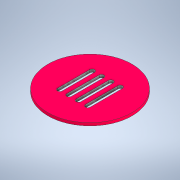
# Autodesk Inventor part: CAPAC_FELINAR_NR_4
Saved by Autodesk Inventor 2022.6 (Build 266554000, 554)
## iProperties
Created: 2025-06-10
Part Number: CAPAC_FELINAR_NR_4
Material: Generic
Document SubType Name: Modeling
Designer: Dragos Macovei
Density: 1 g/cm^3
Appearance: Default
Author: Dragos Macovei
Autodesk Inventor part; units mm, degrees
ref_plane "YZ Plane" through (0, 0, 0) normal (1, 0, 0) x (0, 1, 0)
ref_plane "XZ Plane" through (0, 0, 0) normal (0, 1, 0) x (-1, 0, 0)
ref_plane "XY Plane" through (0, 0, 0) normal (0, 0, 1) x (1, 0, 0)
sketch "Sketch1" plane through (0, 0, 0) normal (0, 1, 0) x (-1, 0, 0)
  circle A0 centre (0, 0) radius 90
  dimension "d0" = 180
  constraints: 1 centre point, 1 coincident
  measures "d0" diameter of A0
extrude "Extrusion1" add sketch "Sketch1" along normal blind 6
sketch "Sketch7" plane through (0, 6, 0) normal (0, 1, 0) x (1, 0, 0)
  circle A0 centre (0, 0) radius 60 construction
  circle A1 centre (30, 34.7214) radius 5
  circle A2 centre (30, -34.7214) radius 5
  line L0 (35, -34.7214) -> (35, 34.7214)
  line L1 (25, 34.7214) -> (25, -34.7214)
  line L2 (-40, 44.7214) -> (40, 44.7214)
  line L3 (40, 44.7214) -> (40, -44.7214)
  line L4 (40, -44.7214) -> (-40, -44.7214)
  line L5 (-40, -44.7214) -> (-40, 44.7214)
  circle A3 centre (-30, 34.7214) radius 5
  circle A4 centre (-30, -34.7214) radius 5
  line L6 (-25, -34.7214) -> (-25, 34.7214)
  line L7 (-35, 34.7214) -> (-35, -34.7214)
  circle A5 centre (-10, 34.7214) radius 5
  circle A6 centre (-10, -34.7214) radius 5
  line L8 (-5, -34.7214) -> (-5, 34.7214)
  line L9 (-15, 34.7214) -> (-15, -34.7214)
  circle A7 centre (10, -34.7214) radius 5
  line L10 (15, -34.7214) -> (15, 34.7214)
  line L11 (5, 34.7214) -> (5, -34.7214)
  circle A8 centre (10, 34.7214) radius 5
  dimension "d25" = 120
  dimension "d26" = 10
  dimension "d27" = 10
  dimension "d28" = 10
  dimension "d29" = 10
  dimension "d30" = 10
  dimension "d31" = 10
  dimension "d32" = 10
  dimension "d33" = 10
  dimension "d34" = 10
  dimension "d35" = 10
  dimension "d36" = 10
  dimension "d37" = 10
  dimension "d38" = 10
  dimension "d39" = 10
  dimension "d40" = 20
  dimension "d41" = 20
  dimension "d42" = 10
  dimension "d43" = 10
  dimension "d44" = 10
  dimension "d45" = 10
  dimension "d46" = 20
  dimension "d47" = 20
  dimension "d48" = 10
  dimension "d49" = 10
  dimension "d50" = 20
  constraints: 24 end point, 19 point on circle, 16 tangent, 9 centre point, 2 parallel, 1 coincident, 1 horizontal, 1 perpendicular
  measures "d25" diameter of A0
  measures "d26" diameter of A1
  measures "d27" diameter of A2
  measures "d28" distance from line of L3 A1.centre
  measures "d29" distance from line of A1.centre L2
  measures "d30" distance from line of L3 A2.centre
  measures "d31" distance from line of L4 A2.centre
  measures "d32" diameter of A3
  measures "d33" diameter of A4
  measures "d34" distance from line of L5 A3.centre
  measures "d35" distance from line of L5 A4.centre
  measures "d36" distance from line of L4 A4.centre
  measures "d37" distance from line of L2 A3.centre
  measures "d38" diameter of A5
  measures "d39" diameter of A6
  measures "d40" distance of A3.centre A5.centre
  measures "d41" distance of A4.centre A6.centre
  measures "d42" distance from line of A5.centre L2
  measures "d43" distance from line of A6.centre L4
  measures "d44" diameter of A8
  measures "d45" diameter of A7
  measures "d46" distance of A6.centre A7.centre
  measures "d47" distance of A5.centre A8.centre
  measures "d48" distance from line of A8.centre L2
  measures "d49" distance from line of L4 A7.centre
  measures "d50" distance of A2.centre A7.centre
extrude "Extrusion3" cut sketch "Sketch7" against normal through all contours A1 | L0 A2 L1 A1 | A2 | A3 | L6 A4 L7 A3 | A4 | A5 | L8 A6 L9 A5 | A6 | A7 | A7 L11 A8 L10 | A8
body "Solid1"
